Autodesk Fusion 360 part; units mm, degrees
(part 3 of 3)
extrude "Trial short M3 insert for GPU tower" cut sketch "草图7 (12)" along normal blind 6.5 bodies 35 in component "18_REAR_BEAM_PCI_TAPERED_END_AND_FRONT_LAP"
ref_plane "工作平面8" through (0, 0, 133.5) normal (0, 0, 1) x (1, 0, 0) in component "18_REAR_BEAM_PCI_TAPERED_END_AND_FRONT_LAP"
sketch "草图8 (10)" plane through (0, 0, 133.5) normal (0, 0, 1) x (1, 0, 0) in component "18_REAR_BEAM_PCI_TAPERED_END_AND_FRONT_LAP"
  circle A0 centre (140, 248.5) radius 2.3
extrude "Trial short M3 insert for GPU tower (1)" cut sketch "草图8 (10)" along normal blind 6.5 bodies 35 in component "18_REAR_BEAM_PCI_TAPERED_END_AND_FRONT_LAP"
ref_plane "工作平面9" through (0, 0, 133.5) normal (0, 0, 1) x (1, 0, 0) in component "18_REAR_BEAM_PCI_TAPERED_END_AND_FRONT_LAP"
sketch "草图9 (9)" plane through (0, 0, 133.5) normal (0, 0, 1) x (1, 0, 0) in component "18_REAR_BEAM_PCI_TAPERED_END_AND_FRONT_LAP"
  circle A0 centre (158, 248.5) radius 2.3
extrude "Trial short M3 insert for GPU tower (2)" cut sketch "草图9 (9)" along normal blind 6.5 bodies 35 in component "18_REAR_BEAM_PCI_TAPERED_END_AND_FRONT_LAP"
ref_plane "工作平面10" through (0, 0, 119.9) normal (0, 0, 1) x (1, 0, 0) in component "18_REAR_BEAM_PCI_TAPERED_END_AND_FRONT_LAP"
sketch "草图10 (7)" plane through (0, 0, 119.9) normal (0, 0, 1) x (1, 0, 0) in component "18_REAR_BEAM_PCI_TAPERED_END_AND_FRONT_LAP"
  line L0 (89, 246.3) -> (103, 246.3)
  line L1 (103, 246.3) -> (103, 248.7)
  line L2 (103, 248.7) -> (89, 248.7)
  line L3 (89, 248.7) -> (89, 246.3)
extrude "Clear exit below GPU metal tab" cut sketch "草图10 (7)" along normal blind 20.2 bodies 35 in component "18_REAR_BEAM_PCI_TAPERED_END_AND_FRONT_LAP"
ref_plane "工作平面11" through (0, 0, 119.9) normal (0, 0, 1) x (1, 0, 0) in component "18_REAR_BEAM_PCI_TAPERED_END_AND_FRONT_LAP"
sketch "草图11 (5)" plane through (0, 0, 119.9) normal (0, 0, 1) x (1, 0, 0) in component "18_REAR_BEAM_PCI_TAPERED_END_AND_FRONT_LAP"
  line L0 (109, 246.3) -> (123, 246.3)
  line L1 (123, 246.3) -> (123, 248.7)
  line L2 (123, 248.7) -> (109, 248.7)
  line L3 (109, 248.7) -> (109, 246.3)
extrude "Clear exit below GPU metal tab (1)" cut sketch "草图11 (5)" along normal blind 20.2 bodies 35 in component "18_REAR_BEAM_PCI_TAPERED_END_AND_FRONT_LAP"
ref_plane "工作平面12" through (0, -253.84, 0) normal (0, 1, 0) x (0, 0, 1) in component "18_REAR_BEAM_PCI_TAPERED_END_AND_FRONT_LAP"
sketch "草图12 (4)" plane through (0, -253.84, 0) normal (0, 1, 0) x (1, 0, 0) in component "18_REAR_BEAM_PCI_TAPERED_END_AND_FRONT_LAP"
  circle A0 through (5.7, -132, 507.68) (3.15, -130.5278, 507.68) (3.15, -133.4722, 507.68)
extrude "M3 screw through beam end ear into side frame" cut sketch "草图12 (4)" along normal blind 8 contours A0 in plane through (0, 253.84, 0) normal (0, 1, 0) bodies 35 in component "18_REAR_BEAM_PCI_TAPERED_END_AND_FRONT_LAP"
ref_plane "工作平面6" through (0, -247.34, 0) normal (0, 1, 0) x (0, 0, 1) in component "16_PCI_INSET_SIDE_16_45mm"
sketch "草图6 (16)" plane through (0, -247.34, 0) normal (0, 1, 0) x (1, 0, 0) in component "16_PCI_INSET_SIDE_16_45mm"
  circle A0 through (6.3, -132, 494.68) (2.85, -130.0081, 494.68) (2.85, -133.9919, 494.68)
extrude "Trial short M3 insert in side frame rear end" cut sketch "草图6 (16)" along normal blind 6.5 contours A0 in plane through (0, 247.34, 0) normal (0, 1, 0) bodies 34 in component "16_PCI_INSET_SIDE_16_45mm"
ref_plane "工作平面7" through (0, -253.84, 0) normal (0, 1, 0) x (0, 0, 1) in component "18_REAR_BEAM_CPU_END_AND_REAR_LAP"
sketch "草图7 (13)" plane through (0, -253.84, 0) normal (0, 1, 0) x (1, 0, 0) in component "18_REAR_BEAM_CPU_END_AND_REAR_LAP"
  circle A0 through (295.7, -132, 507.68) (293.15, -130.5278, 507.68) (293.15, -133.4722, 507.68)
extrude "M3 screw through beam end ear into side frame'" cut sketch "草图7 (13)" along normal blind 8 contours A0 in plane through (0, 253.84, 0) normal (0, 1, 0) bodies 36 in component "18_REAR_BEAM_CPU_END_AND_REAR_LAP"
ref_plane "工作平面4" through (0, -247.34, 0) normal (0, 1, 0) x (0, 0, 1) in component "16_CPU_VERTICAL_SIDE_FLUSH_TO_BEAM"
sketch "草图4 (22)" plane through (0, -247.34, 0) normal (0, 1, 0) x (1, 0, 0) in component "16_CPU_VERTICAL_SIDE_FLUSH_TO_BEAM"
  circle A0 through (296.3, -132, 494.68) (292.85, -130.0081, 494.68) (292.85, -133.9919, 494.68)
extrude "Trial short M3 insert in side frame rear end'" cut sketch "草图4 (22)" along normal blind 6.5 contours A0 in plane through (0, 247.34, 0) normal (0, 1, 0) bodies 33 in component "16_CPU_VERTICAL_SIDE_FLUSH_TO_BEAM"
component "03_FRONT_MOTHERBOARD_BEAM" placed x (1, 0, 0) y (0, 1, 0) z (0, 0, 1) at (0, 0, -50)
component "03_MID_MOTHERBOARD_BEAM" placed x (1, 0, 0) y (0, 1, 0) z (0, 0, 1) at (0, 0, -50)
component "03_REAR_MOTHERBOARD_BEAM" placed x (1, 0, 0) y (0, 1, 0) z (0, 0, 1) at (0, 0, -50)
component "09_FRONT_DUAL_FAN_CARRIER" placed x (1, 0, 0) y (0, 1, 0) z (0, 0, 1) at (0, 0, -50)
component "10_GPU_140_FAN_MOUNT" placed x (1, 0, 0) y (0, 1, 0) z (0, 0, 1) at (0, 0, -50)
component "10_CPU_140_FAN_MOUNT" placed x (1, 0, 0) y (0, 1, 0) z (0, 0, 1) at (0, 0, -50)
component "REF_CASE_FAN_GPU_140x140x25" placed x (1, 0, 0) y (0, 1, 0) z (0, 0, 1) at (0, 0, -50)
component "REF_AIRFLOW_GPU_FRONT_TO_REAR" placed x (1, 0, 0) y (0, 1, 0) z (0, 0, 1) at (0, 0, -50)
component "REF_CASE_FAN_CPU_140x140x25" placed x (1, 0, 0) y (0, 1, 0) z (0, 0, 1) at (0, 0, -50)
component "REF_AIRFLOW_CPU_FRONT_TO_REAR" placed x (1, 0, 0) y (0, 1, 0) z (0, 0, 1) at (0, 0, -50)
component "REF_BOARD_304.8x243.84_NUMBERED_HOLES" placed x (1, 0, 0) y (0, 1, 0) z (0, 0, 1) at (0, 0, -50)
component "REF_CPU_RIGHT" placed x (1, 0, 0) y (0, 1, 0) z (0, 0, 1) at (0, 0, -50)
component "REF_MEMORY_RIGHT_FRONT" placed x (1, 0, 0) y (0, 1, 0) z (0, 0, 1) at (0, 0, -50)
component "REF_PRIMARY_PCIE_X126.4_APPROX" placed x (1, 0, 0) y (0, 1, 0) z (0, 0, 1) at (0, 0, -50)
component "REF_SECOND_LONG_PCIE_X60_APPROX" placed x (1, 0, 0) y (0, 1, 0) z (0, 0, 1) at (0, 0, -50)
component "REF_GPU_FANS_TO_MINUS_X" placed x (1, 0, 0) y (0, 1, 0) z (0, 0, 1) at (0, 0, -50)
component "REF_GPU_FAN_MARKERS_MINUS_X" placed x (1, 0, 0) y (0, 1, 0) z (0, 0, 1) at (0, 0, -50)
component "04_front_GROUND_BAR_290mm_FLAT_PSU" placed x (1, 0, 0) y (0, 1, 0) z (0, 0, 1) at (0, 0, 0)
component "04_rear_GROUND_BAR_290mm_FLAT_PSU" placed x (1, 0, 0) y (0, 1, 0) z (0, 0, 1) at (0, 0, 0)
component "05_CENTERED_FLAT_PSU_CRADLE_OPEN_INTAKE" placed x (1, 0, 0) y (0, 1, 0) z (0, 0, 1) at (0, 0, 0)
component "REF_PSU_FLAT_CENTERED_150x140x86" placed x (1, 0, 0) y (0, 1, 0) z (0, 0, 1) at (0, 0, 0)
component "REF_PSU_INTAKE_DOWN_MINUS_Z" placed x (1, 0, 0) y (0, 1, 0) z (0, 0, 1) at (0, 0, 0)
component "REF_PSU_REAR_EXHAUST_PLUS_Y" placed x (1, 0, 0) y (0, 1, 0) z (0, 0, 1) at (0, 0, 0)
component "12_front_PCI_SUPPORT_FRAME" placed x (1, 0, 0) y (0, 1, 0) z (0, 0, 1) at (0, 0, 0)
component "12_front_CPU_SUPPORT_FRAME" placed x (1, 0, 0) y (0, 1, 0) z (0, 0, 1) at (0, 0, 0)
component "07_GPU_REINFORCED_REAR_TOWER" placed x (1, 0, 0) y (0, 1, 0) z (0, 0, 1) at (0, 0, 0)
component "08_GPU_UPPER_EAR_LEDGE_ADJUSTABLE" placed x (1, 0, 0) y (0, 1, 0) z (0, 0, 1) at (0, 0, 0)
component "08_GPU_LOWER_TWO_TAB_RECEIVER_ADJUSTABLE" placed x (1, 0, 0) y (0, 1, 0) z (0, 0, 1) at (0, 0, 0)
component "16_CPU_VERTICAL_SIDE_FLUSH_TO_BEAM" placed x (1, 0, 0) y (0, 1, 0) z (0, 0, 1) at (0, 0, 0)
component "16_PCI_INSET_SIDE_16_45mm" placed x (1, 0, 0) y (0, 1, 0) z (0, 0, 1) at (0, 0, 0)
component "18_REAR_BEAM_PCI_TAPERED_END_AND_FRONT_LAP" placed x (1, 0, 0) y (0, 1, 0) z (0, 0, 1) at (0, 0, 0)
component "18_REAR_BEAM_CPU_END_AND_REAR_LAP" placed x (1, 0, 0) y (0, 1, 0) z (0, 0, 1) at (0, 0, 0)
equation "desk_limit = 290 mm" comment "V03 layout review; fixed profiles require regeneration"
equation "footprint_width = 290 mm" comment "V03 layout review; fixed profiles require regeneration"
equation "board_width = 304.8 mm" comment "V03 layout review; fixed profiles require regeneration"
equation "board_depth = 243.84 mm" comment "V03 layout review; fixed profiles require regeneration"
equation "board_bottom_height = 208 mm" comment "V03 layout review; fixed profiles require regeneration"
equation "approx_slot_x = 126.4 mm" comment "V03 layout review; fixed profiles require regeneration"
